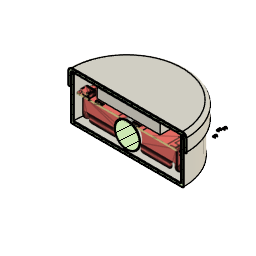
Larp-Button (Autodesk Fusion 360 design; units mm, degrees)
part number: 2026-10-24-12-34-14-010
Autodesk Fusion 360 part; units mm, degrees
sketch "Sketch1" plane through (0, 0, 0) normal (0, 0, 1) x (1, 0, 0)
  circle A0 centre (0, 0) radius 45
  circle A1 centre (0, 0) radius 47.25
  dimension "d1" = 90
  dimension "d2" = 94.5
  constraint coincident A0.centre A1.centre
  measures "d1" diameter of A0
  measures "d2" diameter of A1
extrude "Extrude1" add sketch "Sketch1" along normal blind 38 and the other way blind -25 contours A0 | A1 makes body 1
extrude "Extrude2" add sketch "Sketch1" along normal blind 35 separate body contours A0 makes body 2
fillet "Fillet3" radius 3 1 edges at (-44.0525, -17.0863, 38) on bodies 1
shell "Shell1" thickness 2 removed faces 1 at (-21.1997, 6.8337, 25) on bodies 1
shell "Shell2" thickness 2 removed faces 1 at (4.1569, -25.5535, 35) on bodies 2
chamfer "Chamfer1" distance 0.3 distance2 1 1 edges at (-42.1878, -16.3631, 25) measured on face at (46.239, -4.5955, 25) tangent chain off on bodies 1
fillet "Fillet4" radius 1 1 edges at (-41.9547, -16.2727, 35) on bodies 2
cylinder "CylinderPrimitive1" add diameter 20 height -70 placed x (1, 0, 0) y (0, 0, -1) z (0, 1, 0) at (0, 0, 10) separate body makes body 3
move_body "Move1" bodies 3 to x (1, 0, 0) y (0, 1, 0) z (0, 0, 1) at (0, 35, 4)
box "BoxPrimitive1" add length 19 width 50.4 height 8 placed x (0, 1, 0) y (-1, 0, 0) z (0, 0, 1) at (25.6, -10, 2) separate body makes body 4
move_body "Move2" bodies 4 to x (1, 0, 0) y (0, 1, 0) z (0, 0, 1) at (0, 11, 24)
copy_body "CopyPasteBodies1" bodies 4 makes body 5
move_body "Move3" bodies 5 to x (1, 0, 0) y (0, 1, 0) z (0, 0, 1) at (0, 0, 0)
move_body "Move4" bodies 5 to x (1, 0, 0) y (0, 1, 0) z (0, 0, 1) at (0, -22, 0)
other "Base Mesh Feature1"
equation "d1 = ID"
equation "d2 = ID + thick * 2 + clearance * 2"
equation "d7 = thick"
equation "d12 = thick"
equation "ID = 90 mm"
equation "thick = 2 mm"
equation "clearance = 0.25 mm"
